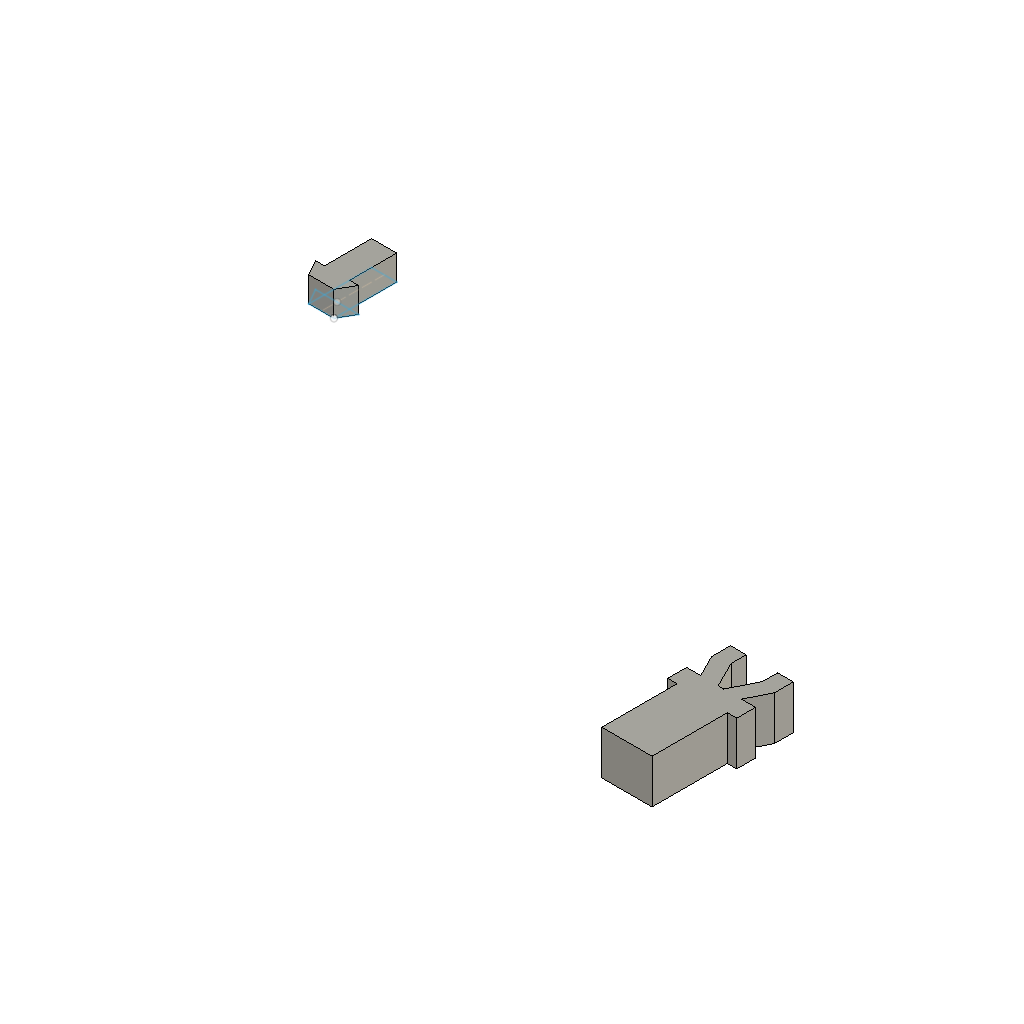
Jazette (Autodesk Fusion 360 archive; units mm, degrees)
design "latches"
Autodesk Fusion 360 part; units mm, degrees
sketch "Sketch1" plane through (0, 0, 0) normal (0, 0, 1) x (1, 0, 0)
  line L0 (-97.5391, 50.2885) -> (-93.5391, 50.2885)
  line L1 (-93.5391, 50.2885) -> (-93.5391, 40.2885)
  line L2 (-93.5391, 40.2885) -> (-97.5391, 40.2885)
  line L3 (-97.5391, 40.2885) -> (-97.5391, 50.2885)
  line L4 (-95.5391, 50.2885) -> (-95.5391, 40.2885) construction
  line L5 (-97.5391, 40.2885) -> (-98.9825, 42.7885)
  line L6 (-98.9825, 42.7885) -> (-95.5391, 42.7885)
  line L7 (-93.5391, 40.2885) -> (-92.0957, 42.7885)
  line L8 (-92.0957, 42.7885) -> (-95.5391, 42.7885)
  dimension "d1" = 4
  dimension "d2" = 30
  dimension "d3" = 2.5
  dimension "d4" = 10
  constraint horizontal L0
  constraint vertical L1
  constraint horizontal L2
  constraint vertical L3
  constraint midpoint L0 L4.start
  constraint midpoint L2 L4.end
  constraint coincident L4 L6.end
  constraint perpendicular L4 L6
  constraint symmetric L2.end L4 L1.end
  constraint symmetric L4 L5.end L7.end
  constraint symmetric L4 L6.end L8.end
  measures "d1" distance of L1 L3
  measures "d2" angle of L3 L5
  measures "d3" distance of L2 L6
  measures "d4" distance of L0.start L2.end
extrude "Extrude1" add sketch "Sketch1" along normal blind 4 makes body 1
sketch "Sketch2" plane through (0, 0, 0) normal (0, 0, 1) x (1, 0, 0)
  line L0 (-10.2967, 13.2155) -> (0.7033, 13.2155)
  line L1 (0.7033, 13.2155) -> (0.7033, 10.2155)
  line L2 (-0.7967, -1.7845) -> (-8.7967, -1.7845)
  line L3 (-10.2967, 10.2155) -> (-10.2967, 13.2155)
  line L4 (-8.7967, -1.7845) -> (-0.7967, -1.7845)
  line L5 (-0.7967, -1.7845) -> (-0.7967, 10.2155)
  line L6 (-8.7967, 10.2155) -> (-8.7967, -1.7845)
  line L7 (-4.7967, 13.2155) -> (-4.7967, -1.7845) construction
  line L8 (-8.7967, 10.2155) -> (-10.2967, 10.2155)
  line L9 (-0.7967, 10.2155) -> (0.7033, 10.2155)
  line L10 (0.2033, 13.2155) -> (-9.7967, 13.2155)
  line L11 (-9.7967, 16.7155) -> (-9.7967, 19.7155)
  line L12 (-8.0467, 19.7155) -> (-1.5467, 19.7155) construction
  line L13 (-1.5467, 19.7155) -> (-1.5467, 13.2155) construction
  line L14 (-1.5467, 13.2155) -> (-8.0467, 13.2155) construction
  line L15 (-8.0467, 13.2155) -> (-8.0467, 19.7155) construction
  line L16 (-9.7967, 16.7155) -> (-8.0467, 13.2155)
  line L17 (-7.2967, 19.7155) -> (-7.2967, 17.3056)
  line L18 (-7.2967, 17.3056) -> (-5.2516, 13.2155)
  line L19 (-9.7967, 19.7155) -> (-7.2967, 19.7155)
  line L20 (0.2033, 16.7155) -> (-1.5467, 13.2155)
  line L21 (0.2033, 16.7155) -> (0.2033, 19.7155)
  line L22 (0.2033, 19.7155) -> (-2.2967, 19.7155)
  line L23 (-2.2967, 19.7155) -> (-2.2967, 17.3056)
  line L24 (-2.2967, 17.3056) -> (-4.3417, 13.2155)
  dimension "d7" = 11
  dimension "d9" = 8
  dimension "d11" = 15
  dimension "d13" = 6.5
  dimension "d14" = 6.5
  dimension "d15" = 3
  dimension "d16" = 2.5
  dimension "d17" = 2.5
  constraint horizontal L0
  constraint vertical L1
  constraint horizontal L2
  constraint vertical L3
  constraint horizontal L4
  constraint vertical L5
  constraint vertical L6
  constraint midpoint L0 L7.start
  constraint symmetric L5 L6 L7
  constraint perpendicular L3 L8
  constraint perpendicular L1 L9
  constraint coincident L2 L7.end
  constraint horizontal L19
  constraint horizontal L10
  constraint vertical L11
  constraint coincident L0 L10.start
  constraint horizontal L12
  constraint vertical L13
  constraint horizontal L14
  constraint vertical L15
  constraint coincident L0 L13.end
  constraint coincident L12.start L19
  constraint symmetric L7 L13 L15
  constraint perpendicular L17 L19
  constraint coincident L14 L18.end
  constraint parallel L16 L18
  constraint symmetric L7 L11.end L21.end
  constraint symmetric L7 L14.end L13.end
  constraint symmetric L7 L11.start L20.start
  constraint symmetric L7 L17.start L22.end
  constraint symmetric L7 L17.end L23.end
  constraint symmetric L7 L18.end L24.end
  measures "d7" distance of L0.start L0.end
  measures "d9" distance of L2.end L2.start
  measures "d11" distance of L0 L4
  measures "d13" distance of L0 L19
  measures "d14" distance of L13 L15
  measures "d15" distance of L11.end L11.start
  measures "d16" distance of L11 L17
  measures "d17" distance of L16 L18
extrude "Extrude2" add sketch "Sketch2" along normal blind 7 separate body makes body 2
named bodies: "LatchStandIn"

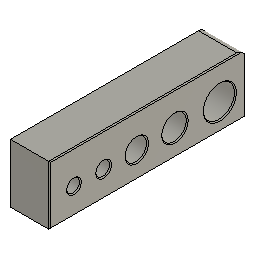
design "Common Design Reference"
Autodesk Fusion 360 part; units mm, degrees
sketch "Sketch1" plane through (0, 0, 0) normal (1, 0, 0) x (0, 1, 0)
  line L0 (0, 0) -> (50, 0)
  line L1 (50, 0) -> (50, -15)
  line L2 (50, -15) -> (0, -15)
  line L3 (0, -15) -> (0, 0)
  circle A0 centre (6.2175, -8.4842) radius 1.625
  circle A1 centre (13.7885, -8.4842) radius 1.75
  circle A2 centre (22.2443, -8.4842) radius 2.75
  circle A3 centre (31.9862, -8.4842) radius 3.125
  line L4 (0, -8.4842) -> (50, -8.4842) construction
  circle A4 centre (43.4421, -8.4842) radius 3.975
  dimension "d1" = 50
  dimension "d2" = 15
  dimension "d10" = 3.25
  dimension "d11" = 3.5
  dimension "d12" = 5.5
  dimension "d13" = 6.25
  dimension "d21" = 7.95
  constraint horizontal L0
  constraint vertical L1
  constraint horizontal L2
  constraint vertical L3
  constraint coincident L0.start L3.end
  constraint coincident L3 L4.start
  constraint coincident L1 L4.end
  constraint perpendicular L1 L4
  constraint coincident A2.centre L4
  constraint coincident A3.centre L4
  constraint coincident L4 A4.centre
  constraint coincident A1.centre L4
  constraint coincident A0.centre L4
  measures "d1" distance of L0.start L0.end
  measures "d2" distance of L0.start L2.end
  measures "d10" diameter of A0
  measures "d11" diameter of A1
  measures "d12" diameter of A2
  measures "d13" diameter of A3
  measures "d21" diameter of A4
extrude "Extrude1" add sketch "Sketch1" along normal blind 10
chamfer "Chamfer1" distance 0.25 angle 45 1 faces at (10, 27.2509, -1.7893) tangent chain off
chamfer "Chamfer2" distance 0.5 angle 45 4 edges at (0, 12.1569, -7.8514) (0, 4.7025, -7.8966) (0, 29.0727, -7.3542) (0, 19.6804, -7.4898) tangent chain off
chamfer "Chamfer2" distance 0.5 angle 45 1 edges at (0, 39.7361, -7.0468) tangent chain off
fillet "Fillet1" radius 2 1 edges at (4.875, 50, 0)
equation "M2_5HeatsetDiam = 3.25 mm"
equation "M3HeatsetDiam = 3.5 mm"
equation "M4HeatsetDiam = 5.5 mm"
equation "M5HeatsetDiam = 6.25 mm"
equation "Clearance = 0.01 mm"
equation "d10 = M2_5HeatsetDiam"
equation "d11 = M3HeatsetDiam"
equation "d12 = M4HeatsetDiam"
equation "d13 = M5HeatsetDiam"
equation "UndersideChamfer = 0.25 mm"
equation "d17 = UndersideChamfer"
equation "HeatsetChamfer = 0.5 mm"
equation "d19 = HeatsetChamfer"
equation "M6HeatsetDiam = 7.95 mm"
equation "d21 = M6HeatsetDiam"
equation "d22 = HeatsetChamfer"

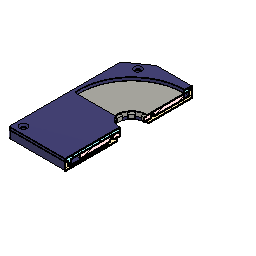
design "Diskette" references "Common Design Reference"
Autodesk Fusion 360 part; units mm, degrees
derive "Derived from Common Design Reference v6" from "Common Design Reference v6"
sketch "Sketch1" plane through (0, 0, 0) normal (0, 0, 1) x (1, 0, 0)
  circle A0 centre (0, 0) radius 35
  circle A1 centre (0, 0) radius 10
  line L0 (37.5, 40) -> (-37.5, 40)
  line L1 (-37.5, 40) -> (-37.5, -45)
  line L2 (-37.5, -45) -> (37.5, -45)
  line L3 (37.5, -45) -> (37.5, 40)
  circle A2 centre (0, 0) radius 15
  circle A3 centre (0, 0) radius 12.5
  line L4 (-2, 10) -> (2, 10)
  line L5 (2, 10) -> (2, 8)
  line L6 (2, 8) -> (-2, 8)
  line L7 (-2, 8) -> (-2, 10)
  line L8 (0, 10) -> (0, 0) construction
  line L9 (0, 40) -> (0, -45) construction
  line L10 (-37.5, 0) -> (37.5, 0) construction
  line L11 (-37.5, 30) -> (-23.2185, 40)
  line L12 (37.5, 30) -> (23.2185, 40)
  circle A4 centre (32.5, -40) radius 1.625
  circle A5 centre (32.5, -40) radius 4
  line L13 (32.2726, -43.9935) -> (32.2726, -45)
  line L14 (32.5, -40) -> (37.5, -40)
  line L15 (32.5, -40) -> (32.2726, -45)
  line L16 (-32.5, -40) -> (-37.5, -40)
  line L17 (-32.2726, -43.9935) -> (-32.2726, -45)
  line L18 (-32.5, -40) -> (-32.2726, -45)
  circle A6 centre (-32.5, -40) radius 4
  circle A7 centre (-32.5, -40) radius 1.625
  circle A8 centre (-27.3947, 31.5823) radius 4
  circle A9 centre (-27.3947, 31.5823) radius 1.625
  circle A10 centre (27.3947, 31.5823) radius 4
  circle A11 centre (27.3947, 31.5823) radius 1.625
  line L19 (-30.3593, 35) -> (0, 0) construction
  dimension "d1" = 70
  dimension "d2" = 20
  dimension "d5" = 75
  dimension "d6" = 85
  dimension "d7" = 30
  dimension "d8" = 25
  dimension "d24" = 2
  dimension "d25" = 2
  dimension "d26" = 2
  dimension "d40" = 40
  dimension "d44" = 55
  dimension "d45" = 10
  dimension "d67" = 3.25
  dimension "d68" = 5
  dimension "d69" = 5
  dimension "d70" = 8
  dimension "d78" = 8
  dimension "d79" = 3.25
  dimension "d81" = 4.5
  constraint coincident A0.centre A1.centre
  constraint concentric A0 A1
  constraint horizontal L0
  constraint perpendicular L0 L1
  constraint parallel L0 L2
  constraint parallel L1 L3
  constraint concentric A2 A3
  constraint horizontal L4
  constraint vertical L5
  constraint horizontal L6
  constraint vertical L7
  constraint tangent A1 L4
  constraint coincident A1 L8.start
  constraint coincident L4 L8.start
  constraint midpoint L0 L9.start
  constraint midpoint L2 L9.end
  constraint coincident L1 L10.start
  constraint coincident L3 L10.end
  constraint perpendicular L3 L10
  constraint coincident A0.centre L9
  constraint coincident A0.centre L10
  constraint coincident L1 L11.start
  constraint coincident L0 L11.end
  constraint symmetric L9 L11.start L12.start
  constraint symmetric L9 L11.end L12.end
  constraint concentric A4 A5
  constraint coincident A5 L13.start
  constraint coincident L2 L13.end
  constraint perpendicular L2 L13
  constraint coincident A4.centre A5.centre
  constraint coincident L3 L14.end
  constraint perpendicular L3 L14
  constraint symmetric L9 A4 A7
  constraint symmetric L9 A5 A6
  constraint symmetric L9 L13.start L17.start
  constraint symmetric L9 L13.end L17.end
  constraint symmetric L9 A4.centre L16.start
  constraint symmetric L9 L14.end L16.end
  constraint symmetric L9 A8 A10
  constraint symmetric L9 A9 A11
  constraint concentric A8 A9
  constraint midpoint L11 L19.start
  constraint coincident A8.centre L19
  measures "d1" diameter of A0
  measures "d2" diameter of A1
  measures "d5" distance of L1.end L2.end
  measures "d6" distance of L0.end L1.end
  measures "d7" diameter of A2
  measures "d8" diameter of A3
  measures "d24" distance of L4 L6
  measures "d25" distance of L7 L8
  measures "d26" distance of L5 L8
  measures "d40" distance of L0 L10
  measures "d44" angle of L1 L11
  measures "d45" distance of L0.end L11.start
  measures "d67" diameter of A4
  measures "d68" distance of L2 A4.centre
  measures "d69" distance of L3 A4.centre
  measures "d70" diameter of A5
  measures "d78" diameter of A8
  measures "d79" diameter of A9
  measures "d81" distance of L11 A8.centre
extrude "Extrude1" add sketch "Sketch1" along normal blind 3 contours A0 | A1 L4 L5 | A1 L4 L7 | A2 | A3 makes body 1
extrude "Extrude2" cut sketch "Sketch1" along normal blind 2 contours A2 bodies 1
extrude "Extrude3" add sketch "Sketch1" against normal blind 2 separate body contours A0 | A1 L4 L5 | A1 L4 L7 | L0 L1 L2 L3 L11 L12 A5 L13 L14 L16 L17 A6 | L2 L3 A5 L14 L15 | A4 A5 L14 L15 | A4 A5 L14 L15 | L1 L2 L16 L18 A6 | A5 L13 L15 | A4 L14 L15 | A4 L14 L15 | L16 L18 A6 A7 | L16 L18 A6 A7 | L17 L18 A6 | L16 L18 A7 | L16 L18 A7 | A2 | A3 | A8 | A9 | A10 | A11 makes body 2
extrude "Extrude4" add sketch "Sketch1" along normal blind 2 contours A2 bodies 2
chamfer "Chamfer1" distance 1.25 angle 45 2 edges at (-13.9849, -5.4242, 2) (-11.6541, 4.5202, 2) tangent chain off on bodies 2
chamfer "Chamfer2" distance 1.25 angle 45 2 edges at (-13.9849, -5.4242, 2) (-11.6541, 4.5202, 2) tangent chain off on bodies 1
move_face "OffsetFaces1" offset -0.15 4 faces at (14.9814, -0.7477, 0.5002) (-5.9979, 13.2928, 1.1667) (13.3166, -0.6646, 1.5834) (12.4845, -0.6231, 0.5002) on bodies 2
sketch "Sketch2" plane through (0, 0, 3) normal (0, 0, 1) x (-1, 0, 0)
  circle A0 centre (0, 0) radius 10
  circle A1 centre (0, 0) radius 35
  line L0 (-37.5, 45) -> (-37.5, -40)
  line L1 (-37.5, -40) -> (37.5, -40)
  line L2 (37.5, -40) -> (37.5, 45)
  line L3 (37.5, 45) -> (-37.5, 45)
  circle A2 centre (0, 0) radius 10
  circle A3 centre (0, 0) radius 8
  line L4 (37.5, -30) -> (23.2185, -40)
  line L5 (-37.5, -30) -> (-23.2185, -40)
  dimension "d18" = -2
extrude "Extrude5" add sketch "Sketch2" along normal blind 2 separate body contours A0 A2 | A1 | L0 L1 L2 L3 L4 L5 makes body 3
extrude "Extrude6" add sketch "Sketch2" against normal blind 0.75 contours A0 A2 bodies 3
move_face "OffsetFaces2" offset -0.25 1 faces at (-9.9876, 0.4985, 2.5) on bodies 3
extrude "Extrude7" add sketch "Sketch1" along normal blind 2.5 contours A1 L5 L6 L7 picked at (0, 8.6667) bodies 1
chamfer "Chamfer3" distance 0.5 angle 45 2 edges at (2, 8, 1.25) (-2, 8, 1.25) tangent chain off on bodies 1
pattern_circular "C-Pattern1" count 8 over 360 about axis through (0, 0, 1.75) along (0, 0, 1) of "Extrude7", "Chamfer3"
copy_body "Body->Comp1" bodies 1 removing the originals makes body 4 in component "Disc"
copy_body "Body->Comp2" bodies 2 removing the originals makes body 5 in component "Back"
copy_body "Body->Comp3" bodies 3 removing the originals makes body 6 in component "Front"
extrude "Extrude2'" add sketch "Sketch1" along normal blind 3.5 contours L2 L3 A5 L14 L15 | A4 A5 L14 L15 | A4 A5 L14 L15 | L1 L2 L16 L18 A6 | L16 L18 A6 A7 | L16 L18 A6 A7 | A8 | A10 bodies 5 in component "Back"
sketch "Sketch1 (2)" plane through (0, 0, 5) normal (0, 0, 1) x (-1, 0, 0) in component "Front"
  circle A0 centre (0, 0) radius 8
  line L0 (37.5, 45) -> (-37.5, 45)
  line L1 (-37.5, 45) -> (-37.5, -30)
  line L2 (-23.2185, -40) -> (23.2185, -40)
  line L3 (37.5, -30) -> (37.5, 45)
  line L4 (37.5, 7.5) -> (-37.5, 7.5) construction
  line L5 (-37.5, -30) -> (-23.2185, -40)
  line L6 (23.2185, -40) -> (37.5, -30)
  circle A1 centre (0, 0) radius 10
  circle A2 centre (0, 0) radius 35
  line L7 (37.5, 3) -> (-37.5, 3)
  dimension "d49" = 3
  constraint midpoint L3 L4.start
  constraint midpoint L1 L4.end
  constraint coincident L3 L7.start
  constraint coincident L1 L7.end
  constraint perpendicular L1 L7
  measures "d49" distance of A0.centre L7
extrude "Extrude1'" cut sketch "Sketch1 (2)" against normal blind 3 contours A0 A1 L7 | A1 A2 L7 picked at (-9.0651, 2.1415) picked at (-26.6021, 0.3069) bodies 6 in component "Front"
sketch "Sketch1 (3)" plane through (0, 0, 0) normal (0, 0, 1) x (-1, 0, 0) in component "Back"
  line L0 (37.5, -30) -> (37.5, 40)
  line L1 (32.2726, 45) -> (-32.2726, 45)
  line L2 (-37.5, 40) -> (-37.5, -30)
  line L3 (-37.5, -30) -> (-23.2185, -40)
  line L4 (-23.2185, -40) -> (23.2185, -40)
  line L5 (23.2185, -40) -> (37.5, -30)
  circle A0 centre (0, 0) radius 14.85
  line L6 (-32.2726, 45) -> (-32.3183, 43.9959)
  arc A1 (-36.5, 40) -> (-32.3183, 43.9959) centre (-32.5, 40) ccw
  line L7 (-36.5, 40) -> (-37.5, 40)
  line L8 (37.5, 40) -> (36.5, 40)
  arc A2 (32.3183, 43.9959) -> (36.5, 40) centre (32.5, 40) ccw
  line L9 (32.3183, 43.9959) -> (32.2726, 45)
  circle A3 centre (27.3947, -31.5823) radius 4
  circle A4 centre (-27.3947, -31.5823) radius 4
  line L10 (27.3038, 43) -> (-27.3038, 43)
  arc A5 (-35.5, 34.8038) -> (-27.3038, 43) centre (-32.5, 40) ccw
  line L11 (-35.5, 34.8038) -> (-35.5, -28.9589)
  line L12 (-35.5, -28.9589) -> (-22.5879, -38)
  line L13 (-22.5879, -38) -> (22.5879, -38)
  line L14 (22.5879, -38) -> (35.5, -28.9589)
  line L15 (35.5, -28.9589) -> (35.5, 34.8038)
  arc A6 (27.3038, 43) -> (35.5, 34.8038) centre (32.5, 40) ccw
  dimension "d46" = -2
extrude "Extrude1''" add sketch "Sketch1 (3)" along normal blind 3.5 contours L0 L1 L2 L3 L4 L5 L6 A1 L7 L8 A2 L9 | A3 L14 | A4 L12 picked at (29.8998, -34.029) picked at (-28.7616, -34.3047) bodies 5 in component "Back"
fillet "Fillet2" radius 1 2 edges at (-34.8712, -3, 4) (34.8712, -3, 4) on bodies 6 in component "Front"
fillet "Fillet1" radius 1 2 edges at (37.5, -45, 4) (-37.5, -45, 4) on bodies 6 in component "Front"
fillet "Fillet1'" radius 1 2 edges at (37.5, -45, 0.75) (-37.5, -45, 0.75) on bodies 5 in component "Back"
chamfer "Chamfer1'" distance 0.25 angle 45 1 faces at (-0.2491, -33.324, -2) tangent chain off on bodies 5 in component "Back"
chamfer "Chamfer1''" distance 0.25 angle 45 1 faces at (0, -32.6667, 5) tangent chain off on bodies 6 in component "Front"
extrude "Extrude2''" cut sketch "Sketch1" along normal blind 7 contours A4 L14 L15 | A4 L14 L15 | L16 L18 A7 | L16 L18 A7 | A9 | A11 bodies 6 in component "Front"
chamfer "Chamfer2'" distance 1 angle 45 4 edges at (-28.9098, 32.1699, 5) (-34.015, -39.4124, 5) (30.985, -39.4124, 5) (25.8797, 32.1699, 5) tangent chain off on bodies 6 in component "Front"
sketch "Sketch2 (2)" plane through (0, 0, 0) normal (0, 0, 1) x (-1, 0, 0) in component "Back"
  line L0 (-35.5, -28.9589) -> (-31.3865, -31.8392)
  arc A0 (-26.2709, -35.4212) -> (-31.3865, -31.8392) centre (-27.3947, -31.5823) ccw
  line L1 (-26.2709, -35.4212) -> (-22.5879, -38)
  line L2 (-22.5879, -38) -> (22.5879, -38)
  line L3 (22.5879, -38) -> (26.2709, -35.4212)
  arc A1 (31.3865, -31.8392) -> (26.2709, -35.4212) centre (27.3947, -31.5823) ccw
  line L4 (31.3865, -31.8392) -> (35.5, -28.9589)
  line L5 (35.5, -28.9589) -> (35.5, 34.8038)
  arc A2 (27.3038, 43) -> (35.5, 34.8038) centre (32.5, 40) ccw
  line L6 (27.3038, 43) -> (-27.3038, 43)
  arc A3 (-35.5, 34.8038) -> (-27.3038, 43) centre (-32.5, 40) ccw
  line L7 (-35.5, 34.8038) -> (-35.5, -28.9589)
  circle A4 centre (0, 0) radius 14.85
  circle A5 centre (0, 28.925) radius 13
  line L8 (0, 43) -> (0, 14.85) construction
  dimension "d82" = 26
  constraint midpoint L6 L8.start
  constraint coincident A4 L8.end
  constraint perpendicular L6 L8
  constraint midpoint A5.centre L8
  measures "d82" diameter of A5
extrude "Extrude3'" cut sketch "Sketch2 (2)" against normal blind 0.5 contours A5 bodies 5 in component "Back"
chamfer "Chamfer1'''" distance 0.25 angle 45 1 faces at (26.4991, -2.2356, 3) tangent chain off on bodies 4 in component "Disc"
chamfer "Chamfer2''" distance 0.25 angle 45 1 faces at (28.203, -1.7388, 0) tangent chain off on bodies 4 in component "Disc"
sketch "Sketch2 (3)" plane through (0, 0, 3) normal (0, 0, -1) x (1, 0, 0) in component "Front"
  line L0 (-33.9411, 3) -> (-9.277, 3)
  arc A0 (9.277, 3) -> (-9.277, 3) centre (0, 0) ccw
  line L1 (9.277, 3) -> (33.9411, 3)
  arc A1 (34.9394, 2.0588) -> (33.9411, 3) centre (33.9411, 2) ccw
  arc A2 (-34.9394, 2.0588) -> (34.9394, 2.0588) centre (0, 0) ccw
  arc A3 (-33.9411, 3) -> (-34.9394, 2.0588) centre (-33.9411, 2) ccw
  arc A4 (-36.5, 45) -> (-37.5, 44) centre (-36.5, 44) ccw
  line L2 (-37.5, 44) -> (-37.5, -30)
  line L3 (-37.5, -30) -> (-23.2185, -40)
  line L4 (-23.2185, -40) -> (23.2185, -40)
  line L5 (23.2185, -40) -> (37.5, -30)
  line L6 (37.5, -30) -> (37.5, 44)
  arc A5 (37.5, 44) -> (36.5, 45) centre (36.5, 44) ccw
  line L7 (36.5, 45) -> (-36.5, 45)
  circle A6 centre (27.3947, -31.5823) radius 1.625
  circle A7 centre (32.5, 40) radius 1.625
  circle A8 centre (-27.3947, -31.5823) radius 1.625
  circle A9 centre (-32.5, 40) radius 1.625
  circle A10 centre (-27.3947, -31.5823) radius 1.625
  circle A11 centre (32.5, 40) radius 1.625
  circle A12 centre (-32.5, 40) radius 1.625
  arc A13 (-36.5, 45) -> (-37.5, 44) centre (-36.5, 44) ccw
  line L8 (-36.5, 45) -> (36.5, 45)
  arc A14 (37.5, 44) -> (36.5, 45) centre (36.5, 44) ccw
  line L9 (37.5, 44) -> (37.5, -30)
  line L10 (37.5, -30) -> (23.2185, -40)
  line L11 (23.2185, -40) -> (-23.2185, -40)
  line L12 (-23.2185, -40) -> (-37.5, -30)
  line L13 (-37.5, -30) -> (-37.5, 44)
  arc A15 (31.3865, -31.8392) -> (26.2709, -35.4212) centre (27.3947, -31.5823) ccw
  line L14 (31.3865, -31.8392) -> (35.5, -28.9589)
  line L15 (35.5, -28.9589) -> (35.5, 34.8038)
  arc A16 (27.3038, 43) -> (35.5, 34.8038) centre (32.5, 40) ccw
  line L16 (27.3038, 43) -> (-27.3038, 43)
  arc A17 (-35.5, 34.8038) -> (-27.3038, 43) centre (-32.5, 40) ccw
  line L17 (-35.5, 34.8038) -> (-35.5, -28.9589)
  line L18 (-35.5, -28.9589) -> (-31.3865, -31.8392)
  arc A18 (-26.2709, -35.4212) -> (-31.3865, -31.8392) centre (-27.3947, -31.5823) ccw
  line L19 (-26.2709, -35.4212) -> (-22.5879, -38)
  line L20 (-22.5879, -38) -> (22.5879, -38)
  line L21 (22.5879, -38) -> (26.2709, -35.4212)
  circle A19 centre (27.3947, -31.5823) radius 1.625
  line L22 (22.5, 42.75) -> (-22.5, 42.75)
  line L23 (-22.5, 42.75) -> (-22.5, 40.75)
  line L24 (-22.5, 40.75) -> (22.5, 40.75)
  line L25 (22.5, 40.75) -> (22.5, 42.75)
  line L26 (22.5879, -35.75) -> (12.5879, -35.75)
  line L27 (12.5879, -35.75) -> (12.5879, -37.75)
  line L28 (12.5879, -37.75) -> (22.5879, -37.75)
  line L29 (22.5879, -37.75) -> (22.5879, -35.75)
  line L30 (35.25, 30) -> (33.25, 30)
  line L31 (33.25, 30) -> (33.25, 15)
  line L32 (33.25, 15) -> (35.25, 15)
  line L33 (35.25, 15) -> (35.25, 30)
  line L34 (0, 45) -> (0, -40) construction
  line L35 (-35.25, 15) -> (-35.25, 30)
  line L36 (-35.25, 30) -> (-33.25, 30)
  line L37 (-33.25, 15) -> (-35.25, 15)
  line L38 (-33.25, 30) -> (-33.25, 15)
  line L39 (-22.5879, -37.75) -> (-22.5879, -35.75)
  line L40 (-22.5879, -35.75) -> (-12.5879, -35.75)
  line L41 (-12.5879, -37.75) -> (-22.5879, -37.75)
  line L42 (-12.5879, -35.75) -> (-12.5879, -37.75)
  dimension "d89" = 2
  dimension "d90" = 0.25
  dimension "d91" = 15
  dimension "d92" = 15
  dimension "d93" = 15
  dimension "d94" = 15
  dimension "d95" = 2
  dimension "d96" = 0.25
  dimension "d97" = 2
  dimension "d98" = 0.25
  dimension "d99" = 10
  constraint horizontal L22
  constraint vertical L23
  constraint horizontal L24
  constraint vertical L25
  constraint horizontal L26
  constraint vertical L27
  constraint horizontal L28
  constraint vertical L29
  constraint horizontal L30
  constraint vertical L31
  constraint horizontal L32
  constraint vertical L33
  constraint midpoint L8 L34.start
  constraint midpoint L11 L34.end
  constraint collinear L20.end L26.start L28.end
  constraint symmetric L26.start L34 L39.end
  constraint symmetric L26.end L34 L40.end
  constraint symmetric L27.end L34 L41.start
  constraint symmetric L28.end L34 L39.start
  constraint symmetric L30.start L34 L35.end
  constraint symmetric L30.end L34 L36.end
  constraint symmetric L31.end L34 L37.start
  constraint symmetric L32.end L34 L35.start
  measures "d89" distance of L22 L24
  measures "d90" distance of L16 L22
  measures "d91" distance of L2 L23
  measures "d92" distance of L9 L25
  measures "d93" distance of L30 L32
  measures "d94" distance of L8 L30
  measures "d95" distance of L31 L33
  measures "d96" distance of L15 L33
  measures "d97" distance of L26 L28
  measures "d98" distance of L20 L28
  measures "d99" distance of L27 L29
extrude "Extrude3''" add sketch "Sketch2 (3)" along normal blind 2 contours L22 L23 L24 L25 | L26 L27 L28 L29 | L30 L31 L32 L33 | L35 L36 L37 L38 | L39 L40 L41 L42 bodies 6 in component "Front"
chamfer "Chamfer3'" distance 0.5 angle 45 5 edges at (35.25, -22.5, 1) (0, -42.75, 1) (-35.25, -22.5, 1) (-17.5879, 37.75, 1) (17.5879, 37.75, 1) tangent chain off on bodies 6 in component "Front"
component "Disc" placed x (1, 0, 0) y (0, 1, 0) z (0, 0, 1) at (0, 0, 0)
component "Back" placed x (1, 0, 0) y (0, 1, 0) z (0, 0, 1) at (0, 0, 0)
component "Front" placed x (1, 0, 0) y (0, 1, 0) z (0, 0, 1) at (0, 0, 0)
equation "d1 = DiscDiam"
equation "d3 = DiscThickness"
equation "d5 = DiscODWidth"
equation "d6 = DiscODHeight"
equation "DiscODWidth = 75 mm"
equation "DiscODHeight = 85 mm"
equation "Hub = 10 mm"
equation "DiscDiam = DiscODWidth - 5 mm"
equation "d40 = ( DiscDiam / 2 ) + 5 mm"
equation "DiscThickness = 3 mm"
equation "d47 = InternalThickness"
equation "M2_5HeatsetDiam_Ref = 3.25 mm"
equation "M3HeatsetDiam_Ref = 3.5 mm"
equation "M4HeatsetDiam_Ref = 5.5 mm"
equation "M5HeatsetDiam_Ref = 6.25 mm"
equation "Clearance_Ref = 0.01 mm"
equation "UndersideChamfer_Ref = 0.25 mm"
equation "HeatsetChamfer_Ref = 0.5 mm"
equation "M6HeatsetDiam_Ref = 7.95 mm"
equation "d67 = M2_5HeatsetDiam_Ref"
equation "d71 = InternalThickness"
equation "d79 = M2_5HeatsetDiam_Ref"
equation "InternalThickness = DiscThickness + 0.5 mm"
